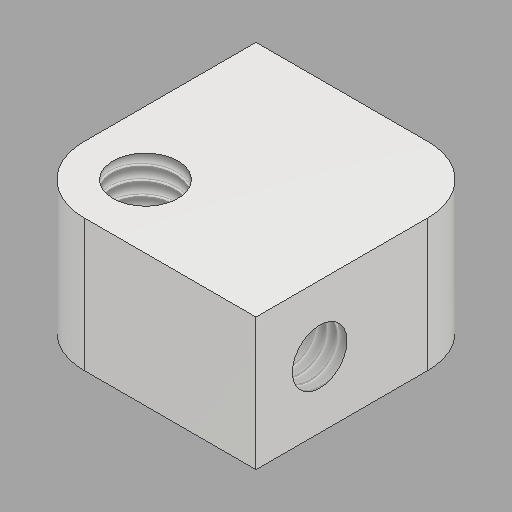
# Autodesk Inventor part: BT024_thutrn22_26_Biegeroboter_halterung_motor
Saved by Autodesk Inventor 2025.3 (Build 293356000, 356)
## iProperties
Company: HTBLA Kaindorf
RuleStatus: InUse
Created: 2026-08-19
Part Number: BT024_thutrn22_26_Biegeroboter_halterung_motor
Project: Biegeroboter
Material: ABS-Kunststoff
Description: halterung_motor
Document SubType Name: Modeling
Designer: thutrn22
Density: 1.06 g/cm^3
Appearance: Glatt - Weiß
Mass: 2.86328 g
Surface Area: 16.5389 cm^2
Volume: 2.70121 cm^3
AfterDocNew0: iProperties-Editor_aufrufen
Author: trist
Keywords: 2026
Autodesk Inventor part; units mm, degrees
ref_plane "YZ Plane" through (0, 0, 0) normal (1, 0, 0) x (0, 1, 0)
ref_plane "XZ Plane" through (0, 0, 0) normal (0, 1, 0) x (-1, 0, 0)
ref_plane "XY Plane" through (0, 0, 0) normal (0, 0, 1) x (1, 0, 0)
sketch "Skizze3" plane through (0, 0, 0) normal (0, 0, 1) x (1, 0, 0)
  line L0 (-12.6, 0) -> (12.6, 0) projected
  line L1 (0, -12.6) -> (0, 12.6) projected
  line L2 (-9, 9) -> (9, 9)
  line L3 (9, 9) -> (9, -9)
  line L4 (9, -9) -> (-9, -9)
  line L5 (-9, -9) -> (-9, 9)
  circle A0 centre (4.1802, -4.1802) radius 3
  point P0 (0, 0)
  dimension "d4" = 18
  dimension "d5" = 18
  dimension "d6" = 6
  dimension "d7" = 4.8198
  dimension "d8" = 4.8198
  constraints: 8 end point, 2 parallel, 1 centre point, 1 coincident, 1 horizontal, 1 perpendicular, 2 other
  measures "d4" distance of L3.end L4.end
  measures "d5" distance of L2.end L3.end
  measures "d6" diameter of A0
  measures "d7" distance from line of A0.centre L4
  measures "d8" distance from line of L3 A0.centre
extrude "Extrusion3" add sketch "Skizze3" along normal blind 10 contours L5 L2 L1 L0 | L0 L1 L4 L5 | L1 L2 L3 L0 | L0 L3 L4 L1 | A0
fillet "Rundung1" radius 5 2 edges at (9, -9, 5) (-9, 9, 5)
sketch "Skizze4" plane through (9, 9, 10) normal (0, 1, 0) x (1, 0, 0)
  line L0 (0, 10) -> (0, 0) projected
  line L1 (0, 0) -> (-13, 0) projected
  point P0 (-9, 10)
  point P1 (-4.82, 5)
  dimension "d12" = 4.82
  dimension "d13" = 5
  measures "d12" distance from line of point (-4.82, 5) L0
  measures "d13" distance from line of L1 point (-4.82, 5)
hole "Bohrung1" at (4.18, 9, 5) direction (0, -1, 0) diameter 4.134 depth 9 thread size "M5x0.8" class "6H" standard "ISO Metric profile"
sketch "Skizze5" plane through (-9, -9, 0) normal (-1, 0, 0) x (0, 0, 1)
  line L0 (0, 13) -> (0, 0) projected
  line L1 (0, 0) -> (10, 0) projected
  point P0 (0, 9)
  point P1 (5, 4.82)
  dimension "d21" = 4.82
  dimension "d22" = 5
  measures "d21" distance from line of L1 point (5, 4.82)
  measures "d22" distance from line of L0 point (5, 4.82)
hole "Bohrung2" at (-9, -4.18, 5) direction (1, 0, 0) diameter 4.134 depth 9 thread size "M5x0.8" class "6H" standard "ISO Metric profile"
hole "Bohrung3" at (4.1802, -4.1802, 0) direction (0, 0, 1) diameter 4.917 end through all thread size "M6x1" class "6H" standard "ISO Metric profile"
